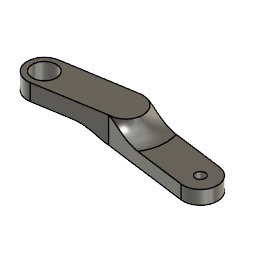
Right Control Arm (Autodesk Fusion 360 design; units mm, degrees)
Autodesk Fusion 360 part; units mm, degrees
sketch "Sketch1" plane through (0, 0, 0) normal (0, 0, 1) x (1, 0, 0)
  circle A0 centre (0, 0) radius 2.2
  circle A1 centre (28.829, 0) radius 0.9
  circle A2 centre (0, 0) radius 3.175
  circle A3 centre (28.829, 0) radius 3.175
  circle A4 centre (12.954, 2.0955) radius 3.175
  line L0 (28.407994, -3.146963) -> (12.954, -1.0795)
  line L1 (0.517136, -3.132602) -> (12.954, -1.0795)
  line L2 (29.244496, 3.147696) -> (13.369496, 5.243196)
  line L3 (-0.507012, 3.134256) -> (12.446988, 5.229756)
  dimension "d1" = 1.8
  dimension "d2" = 4.4
  dimension "d3" = 28.829
  dimension "d4" = 6.35
  dimension "d5" = 6.35
  dimension "d12" = 6.35
  dimension "d22" = 15.875
  dimension "d23" = 2.0955
  constraint coincident A0.centre A2.centre
  constraint concentric A1 A3
  constraint horizontal A0.centre A1.centre
  constraint coincident A4 L0.end
  constraint tangent A4 L2
  constraint tangent A4 L3
  constraint tangent A3 L2
  constraint tangent A3 L0
  constraint tangent A2 L1
  constraint tangent A2 L3
  constraint vertical A4.centre L0.end
  measures "d1" diameter of A1
  measures "d2" diameter of A0
  measures "d3" distance of A0.centre A1.centre
  measures "d4" diameter of A3
  measures "d5" diameter of A2
  measures "d12" diameter of A4
  measures "d22" horizontal distance of A1.centre A4.centre
  measures "d23" vertical distance of A1.centre A4.centre
extrude "Extrude1" add sketch "Sketch1" along normal blind 2.54 contours A4 | A3 A4 L0 L2 | A3 picked at (13.359471, 1.020697) picked at (22.492534, 0.825939) picked at (28.326881, -2.357846)
extrude "Extrude4" add sketch "Sketch1" along normal blind 5.588 contours A4 picked at (13.359471, 1.020697)
extrude "Extrude3" add sketch "Sketch1" along normal blind 5.588 and the other way blind -1.778 contours A2 | A2 A4 L1 L3 | A4 picked at (-0.65517, 2.767544) picked at (7.597762, 1.223874) picked at (13.359471, 1.020697)
extrude "Extrude5" cut 1 faces at (9.192139, 1.492716, 5.588) along direction (0, 0, -1) blind 0.762
fillet "Fillet1" radius 5.08 1 edges at (16.122167, 1.887304, 2.54)
fillet "Fillet2" radius 5.08 1 edges at (9.789202, 1.841177, 1.778)
sketch "Sketch2" plane through (0, 0, 0) normal (0, 0, -1) x (1, 0, 0)
  circle A0 centre (28.2448, 0) radius 1.5
  line L0 (16.8148, -3.175) -> (28.2448, -3.175)
  arc A1 (28.2448, -3.175) -> (28.2448, 3.175) centre (28.2448, 0) ccw
  line L1 (28.2448, 3.175) -> (16.8148, 3.175)
  circle A2 centre (0, 0) radius 2.0955
  circle A3 centre (0, 0) radius 3.175
  arc A4 (16.8148, 3.175) -> (16.8148, -3.175) centre (16.8148, 0) ccw
  dimension "d8" = 4.191
  dimension "d9" = 6.35
  measures "d8" diameter of A2
  measures "d9" diameter of A3
extrude "Extrude2" [suppressed]
equation "d3 = 1.235 in - 0.1 in"
equation "d23 = ( 0.165 / 2 ) * 1 in"
